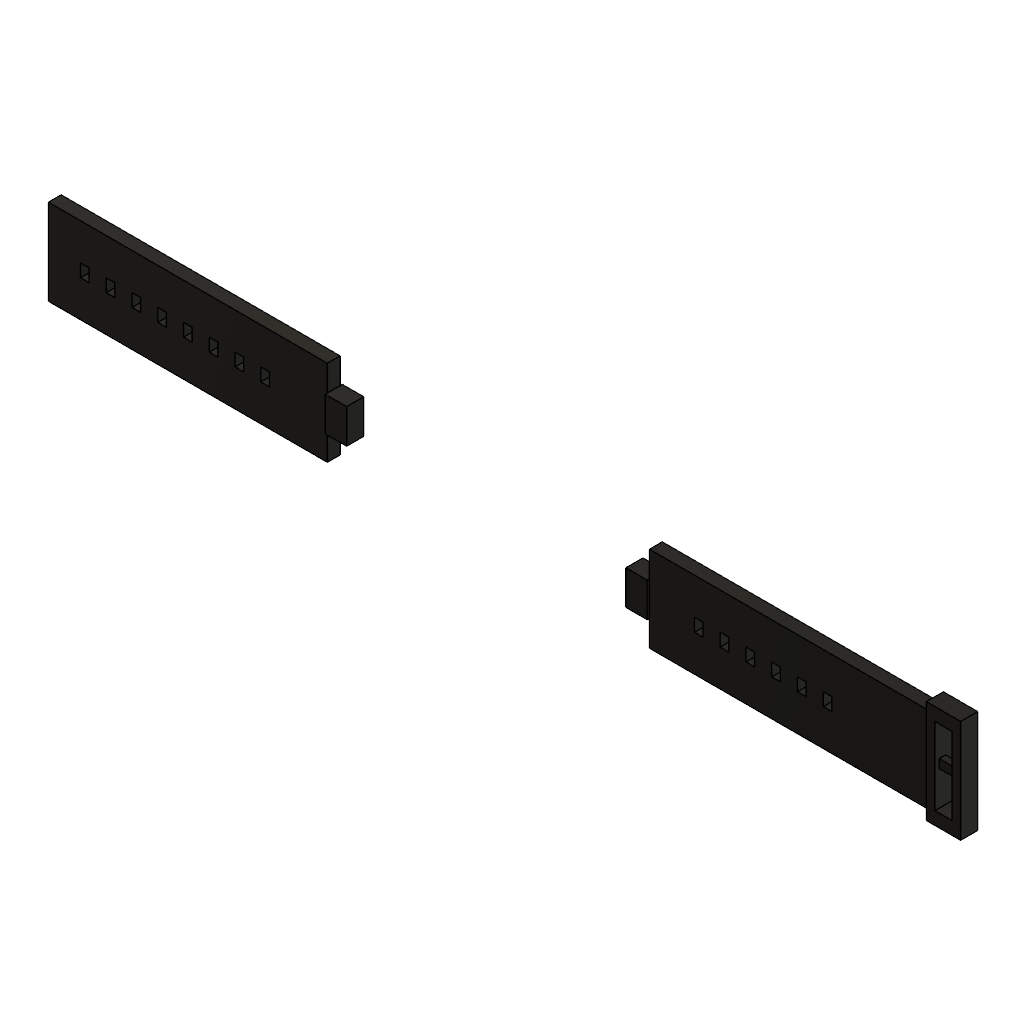
Strap (Autodesk Fusion 360 design; units mm, degrees)
part number: 2026-10-22-09-46-31-519
Autodesk Fusion 360 part; units mm, degrees
sketch "Sketch1" plane through (0, 0, 0) normal (0, 0, 1) x (1, 0, 0)
  line L0 (-102.5, -10) -> (-37.5, -10)
  line L1 (-37.5, -10) -> (-37.5, 10)
  line L2 (-37.5, 10) -> (-102.5, 10)
  line L3 (-102.5, 10) -> (-102.5, -10)
extrude "Extrude1" add sketch "Sketch1" along normal blind 3 makes body 1
sketch "Sketch2" plane through (0, 0, 0) normal (0, 0, 1) x (1, 0, 0)
  line L0 (-37.5, -4) -> (-32.5, -4)
  line L1 (-32.5, -4) -> (-32.5, 4)
  line L2 (-32.5, 4) -> (-37.5, 4)
  line L3 (-37.5, 4) -> (-37.5, -4)
extrude "Extrude2" add sketch "Sketch2" along normal blind 4 from surface at -0.5 bodies 1
sketch "Sketch3" plane through (0, 0, 0) normal (0, 0, 1) x (1, 0, 0)
  line L0 (-95, -1.5) -> (-93, -1.5)
  line L1 (-93, -1.5) -> (-93, 1.5)
  line L2 (-93, 1.5) -> (-95, 1.5)
  line L3 (-95, 1.5) -> (-95, -1.5)
extrude "Extrude3" cut sketch "Sketch3" along normal blind 3 bodies 1
sketch "Sketch4" plane through (0, 0, 0) normal (0, 0, 1) x (1, 0, 0)
  line L0 (-89, -1.5) -> (-87, -1.5)
  line L1 (-87, -1.5) -> (-87, 1.5)
  line L2 (-87, 1.5) -> (-89, 1.5)
  line L3 (-89, 1.5) -> (-89, -1.5)
extrude "Extrude4" cut sketch "Sketch4" along normal blind 3 bodies 1
sketch "Sketch5" plane through (0, 0, 0) normal (0, 0, 1) x (1, 0, 0)
  line L0 (-83, -1.5) -> (-81, -1.5)
  line L1 (-81, -1.5) -> (-81, 1.5)
  line L2 (-81, 1.5) -> (-83, 1.5)
  line L3 (-83, 1.5) -> (-83, -1.5)
extrude "Extrude5" cut sketch "Sketch5" along normal blind 3 bodies 1
sketch "Sketch6" plane through (0, 0, 0) normal (0, 0, 1) x (1, 0, 0)
  line L0 (-77, -1.5) -> (-75, -1.5)
  line L1 (-75, -1.5) -> (-75, 1.5)
  line L2 (-75, 1.5) -> (-77, 1.5)
  line L3 (-77, 1.5) -> (-77, -1.5)
extrude "Extrude6" cut sketch "Sketch6" along normal blind 3 bodies 1
sketch "Sketch7" plane through (0, 0, 0) normal (0, 0, 1) x (1, 0, 0)
  line L0 (-71, -1.5) -> (-69, -1.5)
  line L1 (-69, -1.5) -> (-69, 1.5)
  line L2 (-69, 1.5) -> (-71, 1.5)
  line L3 (-71, 1.5) -> (-71, -1.5)
extrude "Extrude7" cut sketch "Sketch7" along normal blind 3 bodies 1
sketch "Sketch8" plane through (0, 0, 0) normal (0, 0, 1) x (1, 0, 0)
  line L0 (-65, -1.5) -> (-63, -1.5)
  line L1 (-63, -1.5) -> (-63, 1.5)
  line L2 (-63, 1.5) -> (-65, 1.5)
  line L3 (-65, 1.5) -> (-65, -1.5)
extrude "Extrude8" cut sketch "Sketch8" along normal blind 3 bodies 1
sketch "Sketch9" plane through (0, 0, 0) normal (0, 0, 1) x (1, 0, 0)
  line L0 (-59, -1.5) -> (-57, -1.5)
  line L1 (-57, -1.5) -> (-57, 1.5)
  line L2 (-57, 1.5) -> (-59, 1.5)
  line L3 (-59, 1.5) -> (-59, -1.5)
extrude "Extrude9" cut sketch "Sketch9" along normal blind 3 bodies 1
sketch "Sketch10" plane through (0, 0, 0) normal (0, 0, 1) x (1, 0, 0)
  line L0 (-53, -1.5) -> (-51, -1.5)
  line L1 (-51, -1.5) -> (-51, 1.5)
  line L2 (-51, 1.5) -> (-53, 1.5)
  line L3 (-53, 1.5) -> (-53, -1.5)
extrude "Extrude10" cut sketch "Sketch10" along normal blind 3 bodies 1
sketch "Sketch11" plane through (0, 0, 0) normal (0, 0, 1) x (1, 0, 0)
  line L0 (37.5, -10) -> (102.5, -10)
  line L1 (102.5, -10) -> (102.5, 10)
  line L2 (102.5, 10) -> (37.5, 10)
  line L3 (37.5, 10) -> (37.5, -10)
extrude "Extrude11" add sketch "Sketch11" along normal blind 3 separate body makes body 2
sketch "Sketch12" plane through (0, 0, 0) normal (0, 0, 1) x (1, 0, 0)
  line L0 (32.5, -4) -> (37.5, -4)
  line L1 (37.5, -4) -> (37.5, 4)
  line L2 (37.5, 4) -> (32.5, 4)
  line L3 (32.5, 4) -> (32.5, -4)
extrude "Extrude12" add sketch "Sketch12" along normal blind 4 from surface at -0.5 bodies 2
sketch "Sketch13" plane through (0, 0, 0) normal (0, 0, 1) x (1, 0, 0)
  line L0 (48, -1.5) -> (50, -1.5)
  line L1 (50, -1.5) -> (50, 1.5)
  line L2 (50, 1.5) -> (48, 1.5)
  line L3 (48, 1.5) -> (48, -1.5)
extrude "Extrude13" cut sketch "Sketch13" along normal blind 3 bodies 2
sketch "Sketch14" plane through (0, 0, 0) normal (0, 0, 1) x (1, 0, 0)
  line L0 (54, -1.5) -> (56, -1.5)
  line L1 (56, -1.5) -> (56, 1.5)
  line L2 (56, 1.5) -> (54, 1.5)
  line L3 (54, 1.5) -> (54, -1.5)
extrude "Extrude14" cut sketch "Sketch14" along normal blind 3 bodies 2
sketch "Sketch15" plane through (0, 0, 0) normal (0, 0, 1) x (1, 0, 0)
  line L0 (60, -1.5) -> (62, -1.5)
  line L1 (62, -1.5) -> (62, 1.5)
  line L2 (62, 1.5) -> (60, 1.5)
  line L3 (60, 1.5) -> (60, -1.5)
extrude "Extrude15" cut sketch "Sketch15" along normal blind 3 bodies 2
sketch "Sketch16" plane through (0, 0, 0) normal (0, 0, 1) x (1, 0, 0)
  line L0 (66, -1.5) -> (68, -1.5)
  line L1 (68, -1.5) -> (68, 1.5)
  line L2 (68, 1.5) -> (66, 1.5)
  line L3 (66, 1.5) -> (66, -1.5)
extrude "Extrude16" cut sketch "Sketch16" along normal blind 3 bodies 2
sketch "Sketch17" plane through (0, 0, 0) normal (0, 0, 1) x (1, 0, 0)
  line L0 (72, -1.5) -> (74, -1.5)
  line L1 (74, -1.5) -> (74, 1.5)
  line L2 (74, 1.5) -> (72, 1.5)
  line L3 (72, 1.5) -> (72, -1.5)
extrude "Extrude17" cut sketch "Sketch17" along normal blind 3 bodies 2
sketch "Sketch18" plane through (0, 0, 0) normal (0, 0, 1) x (1, 0, 0)
  line L0 (78, -1.5) -> (80, -1.5)
  line L1 (80, -1.5) -> (80, 1.5)
  line L2 (80, 1.5) -> (78, 1.5)
  line L3 (78, 1.5) -> (78, -1.5)
extrude "Extrude18" cut sketch "Sketch18" along normal blind 3 bodies 2
sketch "Sketch19" plane through (0, 0, 0) normal (0, 0, 1) x (1, 0, 0)
  line L0 (102.5, -12) -> (110.5, -12)
  line L1 (110.5, -12) -> (110.5, 12)
  line L2 (110.5, 12) -> (102.5, 12)
  line L3 (102.5, 12) -> (102.5, -12)
extrude "Extrude19" add sketch "Sketch19" along normal blind 4 from surface at -0.5 separate body makes body 3
sketch "Sketch20" plane through (0, 0, 0) normal (0, 0, 1) x (1, 0, 0)
  line L0 (104.5, -9) -> (108.5, -9)
  line L1 (108.5, -9) -> (108.5, 9)
  line L2 (108.5, 9) -> (104.5, 9)
  line L3 (104.5, 9) -> (104.5, -9)
extrude "Extrude20" cut sketch "Sketch20" along normal blind 4 from surface at -0.5 bodies 3
sketch "Sketch21" plane through (0, 0, 0) normal (0, 0, 1) x (1, 0, 0)
  line L0 (102.5, -1) -> (109.5, -1)
  line L1 (109.5, -1) -> (109.5, 1)
  line L2 (109.5, 1) -> (102.5, 1)
  line L3 (102.5, 1) -> (102.5, -1)
extrude "Extrude21" add sketch "Sketch21" along normal blind 1.5 from surface at 1 bodies 2 3
